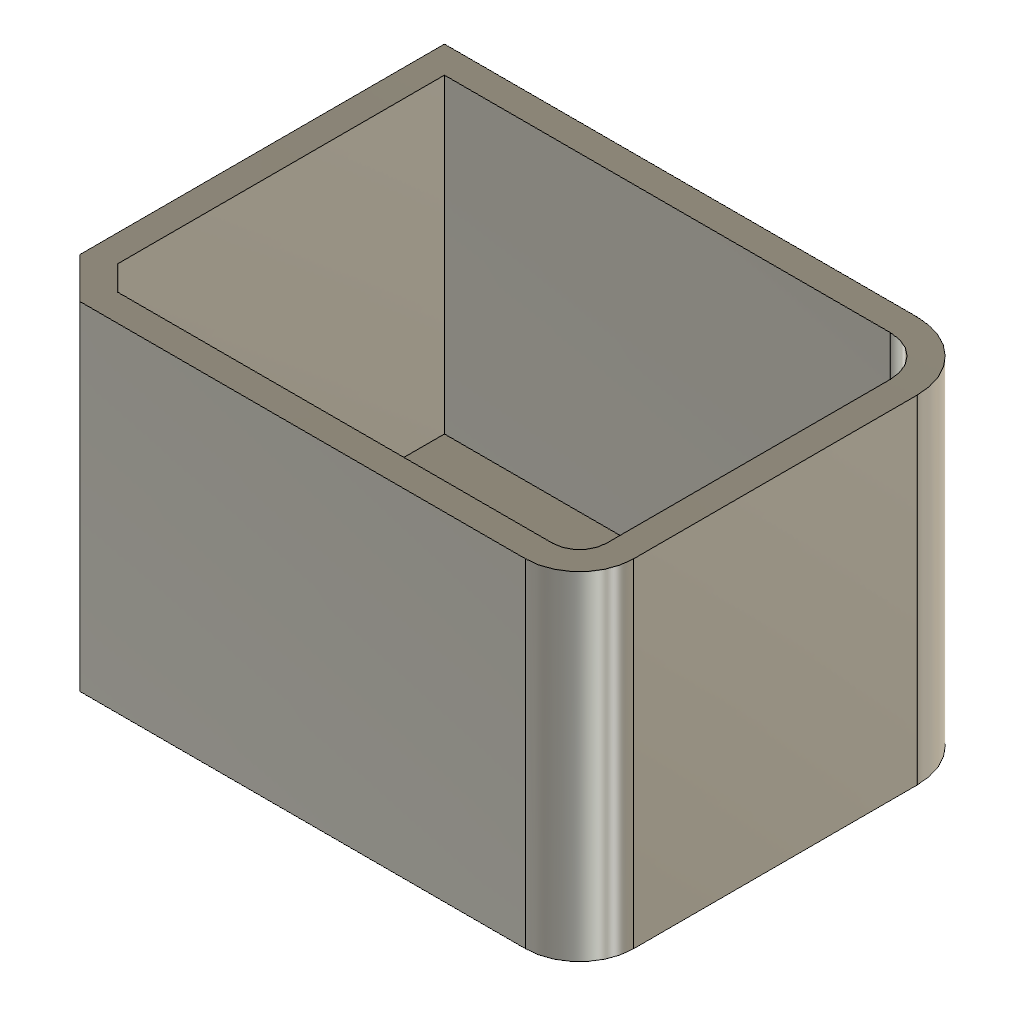
vendor_MultiFeature (Autodesk Fusion 360 design; units mm, degrees)
Autodesk Fusion 360 part; units mm, degrees
sketch "Base Sketch" plane through (0, 0, 0) normal (0, 0, 1) x (1, 0, 0)
  line L0 (0, 0) -> (40, 0)
  line L1 (40, 0) -> (40, 30)
  line L2 (40, 30) -> (0, 30)
  line L3 (0, 30) -> (0, 0)
extrude "Base Extrude" add sketch "Base Sketch" along normal blind 25
fillet "Corner Round" radius 5 1 edges at (40, 30, 12.5)
chamfer "Corner Bevel" distance 3 angle 45 1 edges at (0, 0, 12.5) tangent chain off
fillet "Fillet" radius 4 1 edges at (40, 0, 12.5)
shell "Hollow" thickness 2 removed faces 1 at (12.6667, 20, 25)
equation "height = 20.0 mm"
